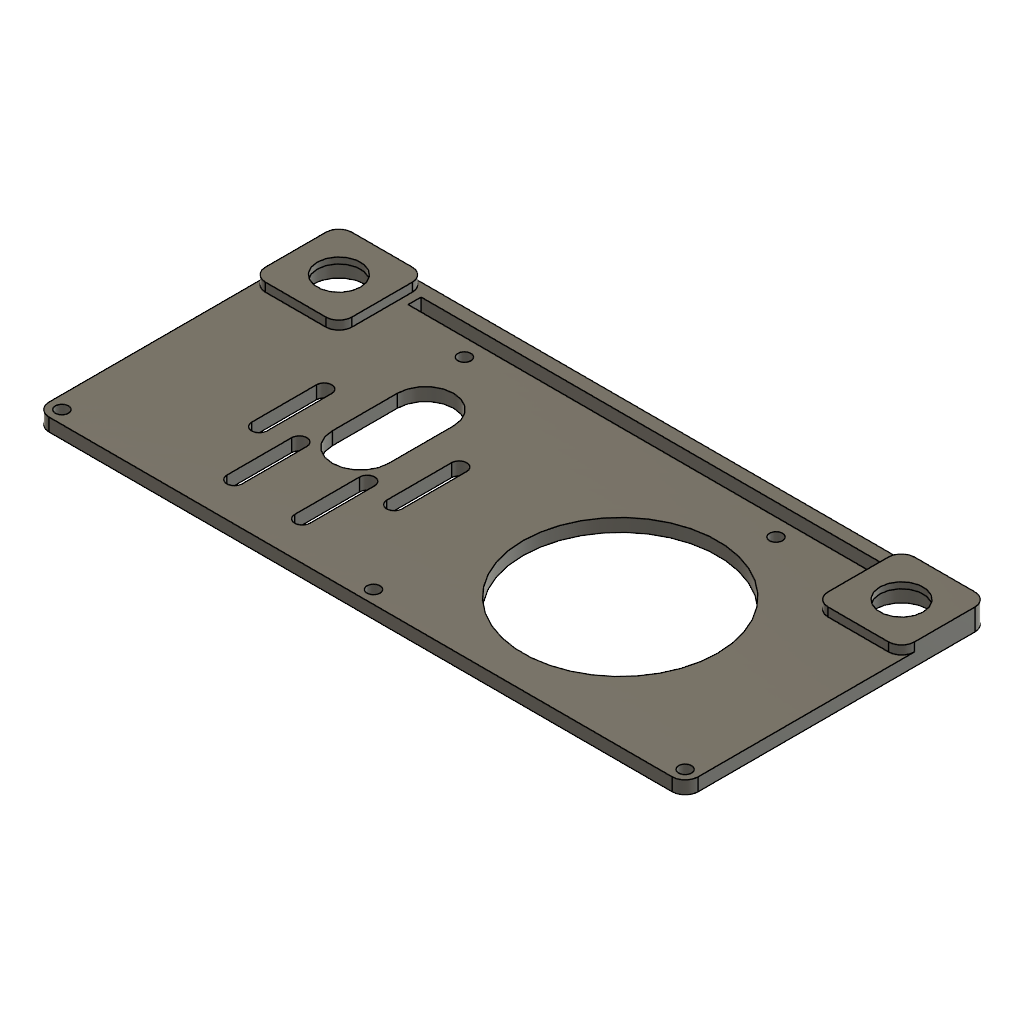
02-01_측판_왼쪽 (Autodesk Fusion 360 design; units mm, degrees)
Autodesk Fusion 360 part; units mm, degrees
sketch "스케치1" plane through (0, 0, 0) normal (0, 1, 0) x (1, 0, 0)
  line L0 (-72, 35) -> (72, 35)
  line L1 (75, 32) -> (75, -32)
  line L2 (72, -35) -> (-72, -35)
  line L3 (-75, -32) -> (-75, 32)
  line L4 (0, 35) -> (0, -35) construction
  line L5 (-75, 0) -> (75, 0) construction
  arc A0 (-72, 35) -> (-75, 32) centre (-72, 32) ccw
  arc A1 (75, 32) -> (72, 35) centre (72, 32) ccw
  arc A2 (72, -35) -> (75, -32) centre (72, -32) ccw
  arc A3 (-75, -32) -> (-72, -35) centre (-72, -32) ccw
  point P0 (-75, 35)
  point P1 (75, 35)
  point P2 (75, -35)
  dimension "d3" = 150
  dimension "d4" = 70
  dimension "d7" = 3
  constraint horizontal L0
  constraint vertical L1
  constraint horizontal L2
  constraint vertical L3
  constraint coincident origin L5
  constraint coincident origin L4
  constraint coincident L3 L5.start
  constraint coincident L0 L4.start
  constraint coincident P0 L3
  constraint coincident P0 L0
  constraint tangent L3 A0
  constraint tangent L0 A0
  constraint coincident L1 L5.end
  constraint coincident P1 L0
  constraint coincident P1 L1
  constraint tangent L0 A1
  constraint tangent L1 A1
  constraint equal A0 A1
  constraint coincident L2 L4.end
  constraint coincident P2 L1
  constraint coincident P2 L2
  constraint tangent L1 A2
  constraint tangent L2 A2
  constraint equal A0 A2
  constraint tangent L2 A3
  constraint tangent L3 A3
  constraint equal A0 A3
  measures "d3" distance of P0 P1
  measures "d4" distance of P1 P2
  measures "d7" radius of A0
extrude "돌출1" add sketch "스케치1" along normal blind 3
sketch "스케치2" plane through (0, 3, 0) normal (0, 1, 0) x (-1, 0, 0)
  arc A0 (72, -35) -> (75, -32) centre (72, -32) ccw
  line L0 (75, -32) -> (75, 32)
  arc A1 (75, 32) -> (72, 35) centre (72, 32) ccw
  line L1 (72, 35) -> (-72, 35)
  arc A2 (-72, 35) -> (-75, 32) centre (-72, 32) ccw
  line L2 (-75, 32) -> (-75, -32)
  arc A3 (-75, -32) -> (-72, -35) centre (-72, -32) ccw
  line L3 (-72, -35) -> (72, -35)
  line L4 (-72, -35) -> (-58, -35)
  line L5 (-55, -32) -> (-55, -18)
  line L6 (-58, -15) -> (-72, -15)
  line L7 (-75, -18) -> (-75, -32)
  arc A4 (-75, -32) -> (-72, -35) centre (-72, -32) ccw
  arc A5 (-72, -15) -> (-75, -18) centre (-72, -18) ccw
  arc A6 (-55, -18) -> (-58, -15) centre (-58, -18) ccw
  arc A7 (-58, -35) -> (-55, -32) centre (-58, -32) ccw
  line L8 (72, -35) -> (58, -35)
  line L9 (55, -32) -> (55, -18)
  line L10 (58, -15) -> (72, -15)
  line L11 (75, -18) -> (75, -32)
  arc A8 (72, -35) -> (75, -32) centre (72, -32) ccw
  arc A9 (55, -32) -> (58, -35) centre (58, -32) ccw
  arc A10 (58, -15) -> (55, -18) centre (58, -18) ccw
  arc A11 (75, -18) -> (72, -15) centre (72, -18) ccw
  point P0 (-75, -35)
  point P1 (-55, -35)
  point P2 (-75, -15)
  point P3 (75, -35)
  point P4 (55, -35)
  point P5 (55, -15)
  dimension "d10" = 20
  dimension "d11" = 20
  dimension "d12" = 3
  dimension "d13" = 20
  dimension "d14" = 20
  dimension "d15" = 3
  constraint horizontal L4
  constraint vertical L5
  constraint horizontal L6
  constraint vertical L7
  constraint coincident P0 L4
  constraint coincident P0 L7
  constraint tangent L4 A4
  constraint tangent L7 A4
  constraint coincident P2 L6
  constraint coincident P2 L7
  constraint tangent L6 A5
  constraint tangent L7 A5
  constraint equal A4 A5
  constraint tangent L6 A6
  constraint tangent L5 A6
  constraint equal A4 A6
  constraint coincident P1 L5
  constraint coincident P1 L4
  constraint tangent L5 A7
  constraint tangent L4 A7
  constraint equal A4 A7
  constraint horizontal L8
  constraint vertical L9
  constraint horizontal L10
  constraint vertical L11
  constraint coincident P3 L11
  constraint coincident P3 L8
  constraint tangent L11 A8
  constraint tangent L8 A8
  constraint coincident P4 L8
  constraint coincident P4 L9
  constraint tangent L8 A9
  constraint tangent L9 A9
  constraint equal A8 A9
  constraint coincident P5 L9
  constraint coincident P5 L10
  constraint tangent L9 A10
  constraint tangent L10 A10
  constraint equal A8 A10
  constraint tangent L10 A11
  constraint tangent L11 A11
  constraint equal A8 A11
  measures "d10" distance of P0 P1
  measures "d11" distance of P0 P2
  measures "d12" radius of A4
  measures "d13" distance of P3 P4
  measures "d14" distance of P4 P5
  measures "d15" radius of A8
extrude "돌출2" add sketch "스케치2" along normal blind 2 contours A0 L0 L3 L8 L9 L10 L11 A8 A9 A10 A11 | L2 A3 L3 L4 L5 L6 L7 A4 A5 A6 A7
sketch "스케치3" plane through (0, 0, 0) normal (0, -1, 0) x (1, 0, 0)
  arc A0 (-75, -32) -> (-72, -35) centre (-72, -32) ccw
  line L0 (-72, -35) -> (72, -35)
  arc A1 (72, -35) -> (75, -32) centre (72, -32) ccw
  line L1 (75, -32) -> (75, 32)
  arc A2 (75, 32) -> (72, 35) centre (72, 32) ccw
  line L2 (72, 35) -> (-72, 35)
  arc A3 (-72, 35) -> (-75, 32) centre (-72, 32) ccw
  line L3 (-75, 32) -> (-75, -32)
  circle A4 centre (65, -25) radius 6.1
  circle A5 centre (-65, -25) radius 6.1
  circle A6 centre (65, -25) radius 5
  circle A7 centre (-65, -25) radius 5
  dimension "d18" = 130
  dimension "d19" = 12.2
  dimension "d20" = 12.2
  dimension "d21" = 25
  dimension "d22" = 10
  dimension "d23" = 10
  dimension "d24" = 10
  constraint concentric A4 A6
  constraint concentric A5 A7
  measures "d18" distance of A4.centre A5.centre
  measures "d19" diameter of A4
  measures "d20" diameter of A5
  measures "d21" vertical distance of origin A5.centre
  measures "d22" distance of L1 A4.centre
  measures "d23" diameter of A6
  measures "d24" diameter of A7
extrude "돌출3" cut sketch "스케치3" against normal blind 5 contours A6 | A7
extrude "돌출4" cut sketch "스케치3" against normal blind 3.6 contours A4 | A5
sketch "스케치4" plane through (0, 3, 0) normal (0, 1, 0) x (-1, 0, 0)
  arc A0 (-72, -15) -> (-75, -18) centre (-72, -18) ccw
  line L0 (-72, -15) -> (-58, -15)
  arc A1 (-55, -18) -> (-58, -15) centre (-58, -18) ccw
  line L1 (-55, -18) -> (-55, -32)
  arc A2 (-58, -35) -> (-55, -32) centre (-58, -32) ccw
  line L2 (-58, -35) -> (58, -35)
  arc A3 (55, -32) -> (58, -35) centre (58, -32) ccw
  line L3 (55, -32) -> (55, -18)
  arc A4 (58, -15) -> (55, -18) centre (58, -18) ccw
  line L4 (58, -15) -> (72, -15)
  arc A5 (75, -18) -> (72, -15) centre (72, -18) ccw
  line L5 (75, -18) -> (75, 32)
  arc A6 (75, 32) -> (72, 35) centre (72, 32) ccw
  line L6 (72, 35) -> (-72, 35)
  arc A7 (-72, 35) -> (-75, 32) centre (-72, 32) ccw
  line L7 (-75, 32) -> (-75, -18)
  line L8 (36.5, -10) -> (36.5, 5)
  arc A8 (36.5, 5) -> (23.5, 5) centre (30, 5) ccw
  line L9 (23.5, 5) -> (23.5, -10)
  arc A9 (23.5, -10) -> (36.5, -10) centre (30, -10) ccw
  line L10 (30, -10) -> (30, 5) construction
  line L11 (36.5, -2.5) -> (23.5, -2.5) construction
  dimension "d29" = 6.5
  dimension "d30" = 15
  dimension "d31" = 30
  dimension "d32" = 2.5
  constraint tangent L8 A8
  constraint tangent A8 L9
  constraint parallel L8 L9
  constraint tangent L9 A9
  constraint tangent L8 A9
  constraint parallel L3 L10
  constraint midpoint L8 L11.start
  constraint midpoint L9 L11.end
  measures "d29" radius of A9
  measures "d30" distance of A8.end L9.end
  measures "d31" horizontal distance of origin A8.centre
  measures "d32" distance of origin L11
extrude "돌출5" cut sketch "스케치4" against normal blind 3 contours L8 A8 L9 A9
sketch "스케치5" plane through (0, 3, 0) normal (0, 1, 0) x (-1, 0, 0)
  line L0 (36.5, 5) -> (36.5, -10)
  arc A0 (23.5, -10) -> (36.5, -10) centre (30, -10) ccw
  line L1 (23.5, -10) -> (23.5, 5)
  arc A1 (36.5, 5) -> (23.5, 5) centre (30, 5) ccw
  arc A2 (-72, -15) -> (-75, -18) centre (-72, -18) ccw
  line L2 (-72, -15) -> (-58, -15)
  arc A3 (-55, -18) -> (-58, -15) centre (-58, -18) ccw
  line L3 (-55, -18) -> (-55, -32)
  arc A4 (-58, -35) -> (-55, -32) centre (-58, -32) ccw
  line L4 (-58, -35) -> (58, -35)
  arc A5 (55, -32) -> (58, -35) centre (58, -32) ccw
  line L5 (55, -32) -> (55, -18)
  arc A6 (58, -15) -> (55, -18) centre (58, -18) ccw
  line L6 (58, -15) -> (72, -15)
  arc A7 (75, -18) -> (72, -15) centre (72, -18) ccw
  line L7 (75, -18) -> (75, 32)
  arc A8 (75, 32) -> (72, 35) centre (72, 32) ccw
  line L8 (72, 35) -> (-72, 35)
  arc A9 (-72, 35) -> (-75, 32) centre (-72, 32) ccw
  line L9 (-75, 32) -> (-75, -18)
  circle A10 centre (30.1918, -2.3934) radius 15.6 construction
  line L10 (38.0181, -15.8882) -> (22.3655, 11.1014) construction
  line L11 (38.0732, 11.0693) -> (22.3104, -15.856) construction
  line L12 (45.7918, -2.3934) -> (14.5918, -2.3934) construction
  line L13 (16.3418, -2.3934) -> (16.3418, 12.6066)
  arc A11 (16.3418, 12.6066) -> (12.8418, 12.6066) centre (14.5918, 12.6066) ccw
  line L14 (12.8418, 12.6066) -> (12.8418, -2.3934)
  arc A12 (12.8418, -2.3934) -> (16.3418, -2.3934) centre (14.5918, -2.3934) ccw
  line L15 (14.5918, -2.3934) -> (14.5918, 12.6066) construction
  line L16 (24.1155, 11.1014) -> (24.1155, 26.1014)
  arc A13 (24.1155, 26.1014) -> (20.6155, 26.1014) centre (22.3655, 26.1014) ccw
  line L17 (20.6155, 26.1014) -> (20.6155, 11.1014)
  arc A14 (20.6155, 11.1014) -> (24.1155, 11.1014) centre (22.3655, 11.1014) ccw
  line L18 (22.3655, 11.1014) -> (22.3655, 26.1014) construction
  line L19 (39.8232, 11.0693) -> (39.8232, 26.0693)
  arc A15 (39.8232, 26.0693) -> (36.3232, 26.0693) centre (38.0732, 26.0693) ccw
  line L20 (36.3232, 26.0693) -> (36.3232, 11.0693)
  arc A16 (36.3232, 11.0693) -> (39.8232, 11.0693) centre (38.0732, 11.0693) ccw
  line L21 (38.0732, 11.0693) -> (38.0732, 26.0693) construction
  line L22 (47.5418, -2.3934) -> (47.5418, 12.6066)
  arc A17 (47.5418, 12.6066) -> (44.0418, 12.6066) centre (45.7918, 12.6066) ccw
  line L23 (44.0418, 12.6066) -> (44.0418, -2.3934)
  arc A18 (44.0418, -2.3934) -> (47.5418, -2.3934) centre (45.7918, -2.3934) ccw
  line L24 (45.7918, -2.3934) -> (45.7918, 12.6066) construction
  dimension "d35" = 31.2
  dimension "d36" = 3.5
  dimension "d37" = 3.5
  dimension "d38" = 3.5
  dimension "d39" = 3.5
  constraint coincident A10 L10.start
  constraint coincident A10 L10.end
  constraint perpendicular A10 L10
  constraint coincident A10 L11.start
  constraint coincident A10 L11.end
  constraint perpendicular A10 L11
  constraint coincident A10 L12.start
  constraint coincident A10 L12.end
  constraint perpendicular A10 L12
  constraint tangent L13 A11
  constraint tangent A11 L14
  constraint parallel L13 L14
  constraint tangent L14 A12
  constraint tangent L13 A12
  constraint perpendicular L12 L15
  constraint coincident L12.end A12.centre
  constraint tangent L16 A13
  constraint tangent A13 L17
  constraint parallel L16 L17
  constraint tangent L17 A14
  constraint tangent L16 A14
  constraint vertical L18
  constraint coincident L10.end A14.centre
  constraint tangent L19 A15
  constraint tangent A15 L20
  constraint parallel L19 L20
  constraint tangent L20 A16
  constraint tangent L19 A16
  constraint vertical L21
  constraint coincident L11.start A16.centre
  constraint tangent L22 A17
  constraint tangent A17 L23
  constraint parallel L22 L23
  constraint tangent L23 A18
  constraint tangent L22 A18
  constraint perpendicular L12 L24
  constraint coincident L12.start A18.centre
  measures "d35" diameter of A10
  measures "d36" diameter of A11
  measures "d37" diameter of A13
  measures "d38" diameter of A15
  measures "d39" diameter of A17
extrude "돌출6" cut sketch "스케치5" against normal blind 3 contours L13 A11 L14 A12 | L16 A13 L17 A14 | L19 A15 L20 A16 | L22 A17 L23 A18
sketch "스케치6" plane through (0, 3, 0) normal (0, 1, 0) x (-1, 0, 0)
  arc A0 (-72, -15) -> (-75, -18) centre (-72, -18) ccw
  line L0 (-72, -15) -> (-58, -15)
  arc A1 (-55, -18) -> (-58, -15) centre (-58, -18) ccw
  line L1 (-55, -18) -> (-55, -32)
  arc A2 (-58, -35) -> (-55, -32) centre (-58, -32) ccw
  line L2 (-58, -35) -> (58, -35)
  arc A3 (55, -32) -> (58, -35) centre (58, -32) ccw
  line L3 (55, -32) -> (55, -18)
  arc A4 (58, -15) -> (55, -18) centre (58, -18) ccw
  line L4 (58, -15) -> (72, -15)
  arc A5 (75, -18) -> (72, -15) centre (72, -18) ccw
  line L5 (75, -18) -> (75, 32)
  arc A6 (75, 32) -> (72, 35) centre (72, 32) ccw
  line L6 (72, 35) -> (-72, 35)
  arc A7 (-72, 35) -> (-75, 32) centre (-72, 32) ccw
  line L7 (-75, 32) -> (-75, -18)
  line L8 (36.5, 5) -> (36.5, -10)
  arc A8 (23.5, -10) -> (36.5, -10) centre (30, -10) ccw
  line L9 (23.5, -10) -> (23.5, 5)
  arc A9 (36.5, 5) -> (23.5, 5) centre (30, 5) ccw
  line L10 (16.3418, 12.6066) -> (16.3418, -2.3934)
  arc A10 (12.8418, -2.3934) -> (16.3418, -2.3934) centre (14.5918, -2.3934) ccw
  line L11 (12.8418, -2.3934) -> (12.8418, 12.6066)
  arc A11 (16.3418, 12.6066) -> (12.8418, 12.6066) centre (14.5918, 12.6066) ccw
  line L12 (47.5418, 12.6066) -> (47.5418, -2.3934)
  arc A12 (44.0418, -2.3934) -> (47.5418, -2.3934) centre (45.7918, -2.3934) ccw
  line L13 (44.0418, -2.3934) -> (44.0418, 12.6066)
  arc A13 (47.5418, 12.6066) -> (44.0418, 12.6066) centre (45.7918, 12.6066) ccw
  line L14 (24.1155, 26.1014) -> (24.1155, 11.1014)
  arc A14 (20.6155, 11.1014) -> (24.1155, 11.1014) centre (22.3655, 11.1014) ccw
  line L15 (20.6155, 11.1014) -> (20.6155, 26.1014)
  arc A15 (24.1155, 26.1014) -> (20.6155, 26.1014) centre (22.3655, 26.1014) ccw
  line L16 (39.8232, 26.0693) -> (39.8232, 11.0693)
  arc A16 (36.3232, 11.0693) -> (39.8232, 11.0693) centre (38.0732, 11.0693) ccw
  line L17 (36.3232, 11.0693) -> (36.3232, 26.0693)
  arc A17 (39.8232, 26.0693) -> (36.3232, 26.0693) centre (38.0732, 26.0693) ccw
  circle A18 centre (-30, 5) radius 22.5
  dimension "d42" = 45
  dimension "d43" = 5
  dimension "d44" = 30
  measures "d42" diameter of A18
  measures "d43" vertical distance of origin A18.centre
  measures "d44" horizontal distance of origin A18.centre
extrude "돌출7" cut sketch "스케치6" against normal blind 3 contours A18
sketch "스케치7" plane through (0, 3, 0) normal (0, 1, 0) x (-1, 0, 0)
  circle A0 centre (-30, 5) radius 22.5
  arc A1 (-72, -15) -> (-75, -18) centre (-72, -18) ccw
  line L0 (-72, -15) -> (-58, -15)
  arc A2 (-55, -18) -> (-58, -15) centre (-58, -18) ccw
  line L1 (-55, -18) -> (-55, -32)
  arc A3 (-58, -35) -> (-55, -32) centre (-58, -32) ccw
  line L2 (-58, -35) -> (58, -35)
  arc A4 (55, -32) -> (58, -35) centre (58, -32) ccw
  line L3 (55, -32) -> (55, -18)
  arc A5 (58, -15) -> (55, -18) centre (58, -18) ccw
  line L4 (58, -15) -> (72, -15)
  arc A6 (75, -18) -> (72, -15) centre (72, -18) ccw
  line L5 (75, -18) -> (75, 32)
  arc A7 (75, 32) -> (72, 35) centre (72, 32) ccw
  line L6 (72, 35) -> (-72, 35)
  arc A8 (-72, 35) -> (-75, 32) centre (-72, 32) ccw
  line L7 (-75, 32) -> (-75, -18)
  line L8 (36.5, 5) -> (36.5, -10)
  arc A9 (23.5, -10) -> (36.5, -10) centre (30, -10) ccw
  line L9 (23.5, -10) -> (23.5, 5)
  arc A10 (36.5, 5) -> (23.5, 5) centre (30, 5) ccw
  line L10 (16.3418, 12.6066) -> (16.3418, -2.3934)
  arc A11 (12.8418, -2.3934) -> (16.3418, -2.3934) centre (14.5918, -2.3934) ccw
  line L11 (12.8418, -2.3934) -> (12.8418, 12.6066)
  arc A12 (16.3418, 12.6066) -> (12.8418, 12.6066) centre (14.5918, 12.6066) ccw
  line L12 (47.5418, 12.6066) -> (47.5418, -2.3934)
  arc A13 (44.0418, -2.3934) -> (47.5418, -2.3934) centre (45.7918, -2.3934) ccw
  line L13 (44.0418, -2.3934) -> (44.0418, 12.6066)
  arc A14 (47.5418, 12.6066) -> (44.0418, 12.6066) centre (45.7918, 12.6066) ccw
  line L14 (24.1155, 26.1014) -> (24.1155, 11.1014)
  arc A15 (20.6155, 11.1014) -> (24.1155, 11.1014) centre (22.3655, 11.1014) ccw
  line L15 (20.6155, 11.1014) -> (20.6155, 26.1014)
  arc A16 (24.1155, 26.1014) -> (20.6155, 26.1014) centre (22.3655, 26.1014) ccw
  line L16 (39.8232, 26.0693) -> (39.8232, 11.0693)
  arc A17 (36.3232, 11.0693) -> (39.8232, 11.0693) centre (38.0732, 11.0693) ccw
  line L17 (36.3232, 11.0693) -> (36.3232, 26.0693)
  arc A18 (39.8232, 26.0693) -> (36.3232, 26.0693) centre (38.0732, 26.0693) ccw
  line L18 (53, -32) -> (-53, -32)
  line L19 (-53, -32) -> (-53, -29)
  line L20 (-53, -29) -> (53, -29)
  line L21 (53, -29) -> (53, -32)
  dimension "d47" = 3
  dimension "d48" = 3
  dimension "d49" = 106
  dimension "d50" = 53
  constraint horizontal L18
  constraint vertical L19
  constraint horizontal L20
  constraint vertical L21
  measures "d47" distance of L2 L18
  measures "d48" distance of L18.end L19.end
  measures "d49" distance of L19.end L20.end
  measures "d50" distance of origin L21
extrude "돌출8" cut sketch "스케치7" against normal blind 3 contours L18 L19 L20 L21
sketch "스케치8" plane through (0, 3, 0) normal (0, 1, 0) x (-1, 0, 0)
  line L0 (-53, -32) -> (-53, -29)
  line L1 (-53, -29) -> (53, -29)
  line L2 (53, -29) -> (53, -32)
  line L3 (53, -32) -> (-53, -32)
  circle A0 centre (-30, 5) radius 22.5
  arc A1 (-72, -15) -> (-75, -18) centre (-72, -18) ccw
  line L4 (-72, -15) -> (-58, -15)
  arc A2 (-55, -18) -> (-58, -15) centre (-58, -18) ccw
  line L5 (-55, -18) -> (-55, -32)
  arc A3 (-58, -35) -> (-55, -32) centre (-58, -32) ccw
  line L6 (-58, -35) -> (58, -35)
  arc A4 (55, -32) -> (58, -35) centre (58, -32) ccw
  line L7 (55, -32) -> (55, -18)
  arc A5 (58, -15) -> (55, -18) centre (58, -18) ccw
  line L8 (58, -15) -> (72, -15)
  arc A6 (75, -18) -> (72, -15) centre (72, -18) ccw
  line L9 (75, -18) -> (75, 32)
  arc A7 (75, 32) -> (72, 35) centre (72, 32) ccw
  line L10 (72, 35) -> (-72, 35)
  arc A8 (-72, 35) -> (-75, 32) centre (-72, 32) ccw
  line L11 (-75, 32) -> (-75, -18)
  line L12 (36.5, 5) -> (36.5, -10)
  arc A9 (23.5, -10) -> (36.5, -10) centre (30, -10) ccw
  line L13 (23.5, -10) -> (23.5, 5)
  arc A10 (36.5, 5) -> (23.5, 5) centre (30, 5) ccw
  line L14 (16.3418, 12.6066) -> (16.3418, -2.3934)
  arc A11 (12.8418, -2.3934) -> (16.3418, -2.3934) centre (14.5918, -2.3934) ccw
  line L15 (12.8418, -2.3934) -> (12.8418, 12.6066)
  arc A12 (16.3418, 12.6066) -> (12.8418, 12.6066) centre (14.5918, 12.6066) ccw
  line L16 (47.5418, 12.6066) -> (47.5418, -2.3934)
  arc A13 (44.0418, -2.3934) -> (47.5418, -2.3934) centre (45.7918, -2.3934) ccw
  line L17 (44.0418, -2.3934) -> (44.0418, 12.6066)
  arc A14 (47.5418, 12.6066) -> (44.0418, 12.6066) centre (45.7918, 12.6066) ccw
  line L18 (24.1155, 26.1014) -> (24.1155, 11.1014)
  arc A15 (20.6155, 11.1014) -> (24.1155, 11.1014) centre (22.3655, 11.1014) ccw
  line L19 (20.6155, 11.1014) -> (20.6155, 26.1014)
  arc A16 (24.1155, 26.1014) -> (20.6155, 26.1014) centre (22.3655, 26.1014) ccw
  line L20 (39.8232, 26.0693) -> (39.8232, 11.0693)
  arc A17 (36.3232, 11.0693) -> (39.8232, 11.0693) centre (38.0732, 11.0693) ccw
  line L21 (36.3232, 11.0693) -> (36.3232, 26.0693)
  arc A18 (39.8232, 26.0693) -> (36.3232, 26.0693) centre (38.0732, 26.0693) ccw
  circle A19 centre (36, -25) radius 1.5
  circle A20 centre (-36, -25) radius 1.5
  circle A21 centre (-72, 32) radius 1.5
  circle A22 centre (0, 32) radius 1.5
  circle A23 centre (72, 32) radius 1.5
  dimension "d53" = 3
  dimension "d54" = 3
  dimension "d55" = 3
  dimension "d56" = 3
  dimension "d57" = 3
  dimension "d58" = 25
  dimension "d59" = 25
  dimension "d60" = 72
  dimension "d61" = 36
  constraint concentric A8 A21
  constraint concentric A7 A23
  measures "d53" diameter of A19
  measures "d54" diameter of A20
  measures "d55" diameter of A21
  measures "d56" diameter of A22
  measures "d57" diameter of A23
  measures "d58" vertical distance of origin A20.centre
  measures "d59" vertical distance of origin A19.centre
  measures "d60" distance of A19.centre A20.centre
  measures "d61" horizontal distance of origin A20.centre
extrude "돌출9" cut sketch "스케치8" against normal blind 3 contours A19 | A20 | A21 | A22 | A23
equation "d20 = d19"
equation "d61 = d60 / 2"
